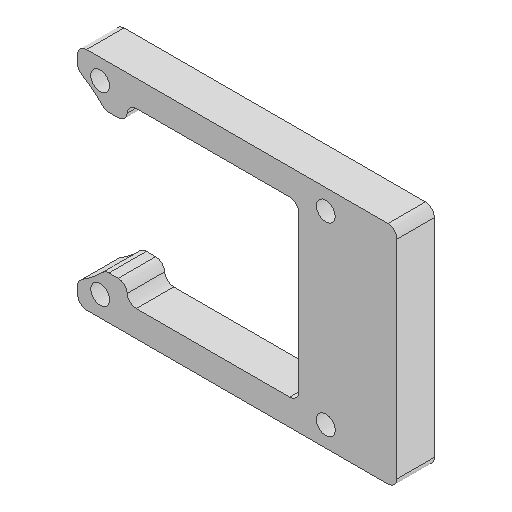
# Autodesk Inventor part: AP3.0_servo-mount
Saved by Autodesk Inventor 2025.3 (Build 293356030, 356C)
## iProperties
Created: 2024-04-22
Part Number: AP3.0_servo-mount
Material: 一般
Document SubType Name: Sheet Metal
Designer: 8326d
Density: 1 g/cm^3
Sheet Metal Rule: Default_mm
Appearance: 既定
Author: 8326d
## iProperties of the stored document T3.0_servo-mount_3D プリント.ipt
Created: 2024-09-23
Part Number: T3.0_servo-mount_3D プリント
Material: 一般
Document SubType Name: Modeling
Designer: 8326d
Density: 1 g/cm^3
Appearance: 既定
Author: 8326d
Autodesk Inventor part; units mm, degrees
ref_plane "YZ Plane" through (0, 0, 0) normal (1, 0, 0) x (0, 1, 0)
ref_plane "XZ Plane" through (0, 0, 0) normal (0, 1, 0) x (-1, 0, 0)
ref_plane "XY Plane" through (0, 0, 0) normal (0, 0, 1) x (1, 0, 0)
sketch "スケッチ1" plane through (0, 0, 0) normal (0, 0, 1) x (1, 0, 0)
  line L0 (-17.6925, -12.5) -> (17.6925, -12.5)
  line L1 (17.6925, -12.5) -> (17.6925, 12.5)
  line L2 (17.6925, 12.5) -> (-17.6925, 12.5)
  line L3 (-17.6925, 12.5) -> (-17.6925, -12.5)
  line L4 (-17.6925, -12.5) -> (17.6925, 12.5) construction
  line L5 (17.6925, -12.5) -> (-17.6925, 12.5) construction
  point P0 (0, 0)
  dimension "d0" = 35.385
  dimension "d1" = 25
  measures "d0" distance of L1.end L2.end
  measures "d1" distance of L0.end L1.end
extrude "プレート1" add sketch "スケッチ1" along normal blind 4.15
sketch "スケッチ2" plane through (0, 0, 4.15) normal (0, 0, 1) x (1, 0, 0)
  line L0 (-15.1925, -10.25) -> (9.8075, -10.25) construction
  line L1 (9.8075, -10.25) -> (9.8075, 10.25) construction
  line L2 (9.8075, 10.25) -> (-15.1925, 10.25) construction
  line L3 (-15.1925, 10.25) -> (-15.1925, -10.25) construction
  line L4 (-15.1925, -10.25) -> (9.8075, 10.25) construction
  line L5 (9.8075, -10.25) -> (-15.1925, 10.25) construction
  line L6 (17.6925, 12.5) -> (17.6925, -12.5) construction
  line L7 (-17.6925, -12.5) -> (-17.6925, 12.5) projected
  point P0 (0, 0)
  point P1 (-2.6925, 0)
  dimension "d3" = 25
  dimension "d4" = 20.5
  dimension "d42" = 2.5
  constraints: 12 end point, 2 midpoint, 2 parallel, 1 horizontal, 1 horizontal alignment, 1 perpendicular
  measures "d3" distance of L2.end L1.end
  measures "d4" distance of L1.end L0.end
  measures "d42" distance between parallel lines of L7 L3
hole "穴1" at (-15.1925, 10.25, 4.15) at (9.8075, 10.25, 4.15) at (9.8075, -10.25, 4.15) at (-15.1925, -10.25, 4.15) direction (0, 0, -1) diameter 2.1 end through all
sketch "スケッチ3" plane through (0, 0, 0) normal (0, 0, -1) x (-1, 0, 0)
  line L0 (-17.6925, -12.5) -> (-17.6925, 12.5) projected
  line L1 (17.6925, 12.5) -> (17.6925, -12.5) projected
  line L2 (-17.6925, 7.7) -> (17.6925, 7.7)
  line L3 (17.6925, -7.7) -> (-17.6925, -7.7)
  line L4 (-17.6925, 12.5) -> (17.6925, 12.5) projected
  line L5 (17.6925, -12.5) -> (-17.6925, -12.5) projected
  line L6 (-12.6925, 7.7) -> (-12.6925, -7.7)
  point P0 (0, 0)
  dimension "d13" = 4.8
  dimension "d14" = 4.8
  dimension "d43" = 5
  constraints: 6 end point, 6 point on line, 4 perpendicular
  measures "d13" distance between parallel lines of L4 L2
  measures "d14" distance between parallel lines of L5 L3
  measures "d43" distance between parallel lines of L0 L6
extrude "押し出し1" cut sketch "スケッチ3" against normal blind 1.5 contours L6 L2 L1 L3
sketch "スケッチ4" plane through (0, 0, 4.15) normal (0, 0, 1) x (1, 0, 0)
  line L0 (-17.6925, 12.5) -> (17.6925, 12.5) projected
  line L1 (17.6925, -12.5) -> (-17.6925, -12.5) projected
  circle A0 centre (-23.1925, 0) radius 11.5
  line L2 (17.6925, 12.5) -> (17.6925, -12.5) projected
  line L3 (6.8075, -9.6) -> (-12.1925, -9.6)
  line L4 (-12.1925, -9.6) -> (-12.1925, 9.6)
  line L5 (-12.1925, 9.6) -> (6.8075, 9.6)
  line L6 (6.8075, 9.6) -> (6.8075, -9.6)
  line L7 (6.8075, -9.6) -> (-12.1925, 9.6) construction
  line L8 (-12.1925, -9.6) -> (6.8075, 9.6) construction
  line L9 (-12.1925, 7.7) -> (-14.6508, 7.7)
  line L10 (-14.6508, 7.7) -> (-14.6508, -7.7)
  line L11 (-14.6508, -7.7) -> (-12.1925, -7.7)
  line L12 (-12.1925, -7.7) -> (-12.1925, 7.7)
  line L13 (12.6925, 7.7) -> (-17.6925, 7.7) projected
  point P0 (0, 0)
  point P1 (17.6925, 0)
  point P2 (-2.6925, 0)
  point P3 (-12.1925, 0)
  point P4 (-14.6508, 7.7)
  point P5 (-12.1925, -7.7)
  point P6 (17.6925, 7.7)
  dimension "d18" = 23
  dimension "d17" = 40.885
  dimension "d20" = 2.9
  dimension "d22" = 19
  dimension "d41" = 11
  constraints: 20 end point, 4 midpoint, 4 parallel, 3 horizontal alignment, 2 horizontal, 2 perpendicular, 1 collinear, 1 point on line, 3 other
  measures "d17" distance from line of L2 point (-23.192, 0)
  measures "d20" distance between parallel lines of L0 L5
  measures "d22" distance between parallel lines of L6 L12
  measures "d41" distance from line of point (-23.192, 0) L12
extrude "押し出し2" cut sketch "スケッチ4" against normal through all
fillet "フィレット1" radius 1 14 edges at (-12.1925, 9.6, 2.075) (-12.1925, -9.6, 2.075) (6.8075, -9.6, 2.075) (6.8075, 9.6, 2.075) (-12.1925, 7.7, 2.075) (-12.1925, -7.7, 2.075) (-14.6508, -7.7, 2.075) (-14.6508, 7.7, 2.075) (-17.6925, -10.0995, 2.075) (-17.6925, 10.0995, 2.075) (-17.6925, -12.5, 2.075) (17.6925, -12.5, 2.075) (17.6925, 12.5, 2.075) (-17.6925, 12.5, 2.075)
fillet "フィレット2" radius 1.2 2 edges at (12.6925, 7.7, 0.75) (12.6925, -7.7, 0.75)
equation "\"d11\" = Thickness"
equation "\"d14\" = d13"
equation "\"d2\" = Thickness"
equation "\"BendRadius\" = Thickness"
equation "\"BendReliefWidth\" = Thickness"
equation "\"BendReliefDepth\" = 0.5 * Thickness"
equation "\"CornerReliefSize\" = 4 * Thickness"
equation "\"MinimumRemnant\" = 2 * Thickness"
equation "\"TransitionRadius\" = BendRadius"
equation "\"JacobiRadiusSize\" = BendRadius"
equation "\"GapSize\" = Thickness"
equation "\"Thickness\" = 4.15"
